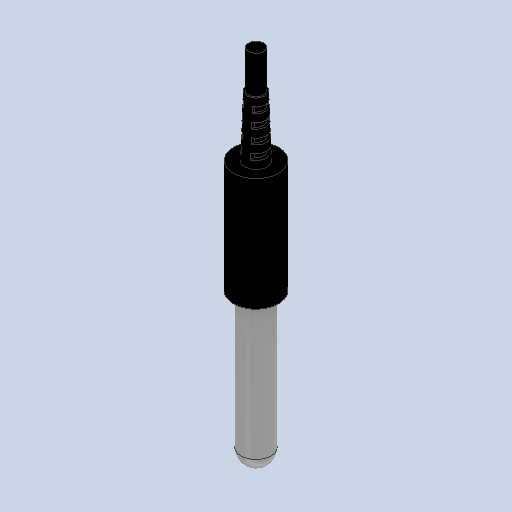
# Autodesk Inventor part: sensore_Temp
Saved by Autodesk Inventor 2026.1 (Build 301233020, 233B)
## iProperties
Created: 2026-01-07
Part Number: sensore_Temp
Material: Generico
Document SubType Name: Modeling
Designer: maxbu
Density: 1 g/cm^3
Appearance: Liscia - Bianco
Author: maxbu
Autodesk Inventor part; units mm, degrees
ref_plane "XZ Plane" through (0, 0, 0) normal (0, 1, 0) x (-1, 0, 0)
ref_plane "XY Plane" through (0, 0, 0) normal (0, 0, 1) x (1, 0, 0)
sketch "Schizzo1" plane through (0, 0, 0) normal (1, 0, 0) x (0, 1, 0)
  line L0 (0, 0) -> (0, -2)
  line L1 (0, -2) -> (20, -2)
  line L2 (20, -2) -> (20, -3)
  line L3 (20, -3) -> (35, -3)
  line L4 (35, -3) -> (35, -1.5)
  line L5 (35, -1.5) -> (43, -1.2)
  line L6 (43, -1.2) -> (43, -1)
  line L7 (43, -1) -> (48, -1)
  line L8 (48, -1) -> (48, 0)
  line L9 (48, 0) -> (0, 0)
  dimension "d1" = 1
  dimension "d2" = 0.2
  dimension "d3" = 8
  dimension "d4" = 2
  dimension "d5" = 3
  dimension "d6" = 20
  dimension "d7" = 15
  dimension "d8" = 5
  dimension "d10" = 1.5
  constraints: 20 end point, 5 perpendicular, 2 horizontal, 2 vertical
  measures "d1" distance of L7.end L8.end
  measures "d2" distance of L5.end L6.end
  measures "d3" horizontal distance of L4.end L5.end
  measures "d4" distance between parallel lines of L9 L1
  measures "d5" distance between parallel lines of L9 L3
  measures "d6" distance of L0.end L1.end
  measures "d7" distance of L2.end L3.end
  measures "d8" distance of L6.end L7.end
  measures "d10" distance of L3.end L4.end
revolve "Rivoluzione1" add sketch "Schizzo1" angle 360 about axis through (0, 48, 0) along (0, -1, 0)
ref_plane "Piano di lavoro1" through (12, 0, 0) normal (1, 0, 0) x (0, 1, 0)
sketch "Schizzo2" plane through (12, 0, 0) normal (1, 0, 0) x (0, 1, 0)
  line L0 (36.75, 5) -> (36, 5)
  line L1 (36, 5) -> (36, -5)
  line L2 (36, -5) -> (36.75, -5)
  line L3 (36.75, -5) -> (36.75, 5)
  line L4 (38.5, 5) -> (37.75, 5)
  line L5 (37.75, 5) -> (37.75, -5)
  line L6 (37.75, -5) -> (38.5, -5)
  line L7 (38.5, -5) -> (38.5, 5)
  line L8 (40.25, 5) -> (39.5, 5)
  line L9 (39.5, 5) -> (39.5, -5)
  line L10 (39.5, -5) -> (40.25, -5)
  line L11 (40.25, -5) -> (40.25, 5)
  line L12 (42, 5) -> (41.25, 5)
  line L13 (41.25, 5) -> (41.25, -5)
  line L14 (41.25, -5) -> (42, -5)
  line L15 (42, -5) -> (42, 5)
  line L16 (41.25, 5) -> (40.25, 5) construction
  line L17 (39.5, 5) -> (38.5, 5) construction
  line L18 (37.75, 5) -> (36.75, 5) construction
  line L19 (35, 3) -> (35, -3) projected
  line L20 (43, 1.2) -> (43, -1.2) projected
  line L21 (41.25, 0) -> (43, 0) construction
  point P0 (0, 0)
  point P1 (35, 0)
  dimension "d12" = 1
  dimension "d13" = 1
  dimension "d14" = 1
  dimension "d15" = 10
  constraints: 40 end point, 11 collinear, 9 equal length, 6 perpendicular, 5 horizontal, 3 midpoint
  measures "d12" distance from line of L19 L0.end
  measures "d13" distance between parallel lines of L15 L20
  measures "d14" distance of L4.end L0.start
  measures "d15" distance between parallel lines of L0 L2
extrude "Estrusione1" cut sketch "Schizzo2" against normal blind 11.4
mirror "Speculare1" about plane through (0, 0, 0) normal (1, 0, 0) of "Estrusione1"
sketch "Schizzo3" plane through (0, 48, 0) normal (0, 1, 0) x (1, 0, 0)
  circle A0 centre (0, 0) radius 1 projected
extrude "Estrusione2" add sketch "Schizzo3" against normal blind 20
fillet "Raccordo1" radius 2 1 edges at (0, 0, 2)
